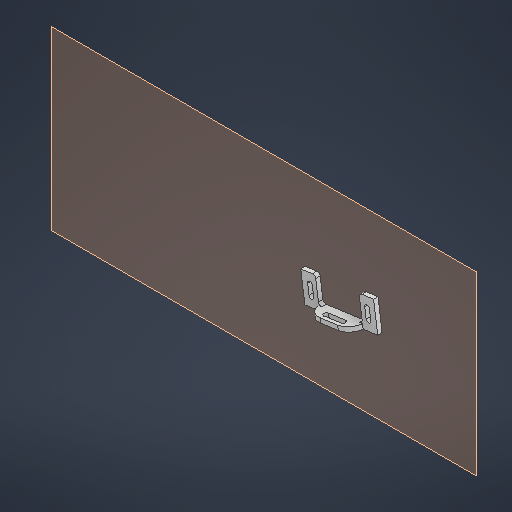
# Autodesk Inventor part: support_cable_aimant
Saved by Autodesk Inventor 2026.1 (Build 301233020, 233B)
## iProperties
Created: 2026-06-08
Part Number: support_cable_aimant
Material: Générique
Document SubType Name: Modeling
Designer: matpo
Density: 1 g/cm^3
Appearance: Par défaut
Author: matpo
Autodesk Inventor part; units mm, degrees
ref_plane "YZ Plane" through (0, 0, 0) normal (1, 0, 0) x (0, 1, 0)
ref_plane "XZ Plane" through (0, 0, 0) normal (0, 1, 0) x (-1, 0, 0)
ref_plane "XY Plane" through (0, 0, 0) normal (0, 0, 1) x (1, 0, 0)
ref_plane "Plan de construction1" through (0, 0, 0) normal (0, 0, 1) x (1, 0, 0)
sketch "Esquisse1" plane through (0, 0, 0) normal (0, 0, 1) x (1, 0, 0)
  line L0 (100.8988, -45.4881) -> (101.7309, -51.4301) projected
  arc A0 (104.0679, -45.0443) -> (100.8988, -45.4881) centre (102.4833, -45.2662) ccw projected
  line L1 (104.9, -50.9863) -> (104.0679, -45.0443) projected
  arc A1 (101.7309, -51.4301) -> (104.9, -50.9863) centre (103.3155, -51.2082) ccw projected
  line L2 (139.72, -40.0515) -> (140.5521, -45.9936) projected
  arc A2 (140.5521, -45.9936) -> (143.7212, -45.5498) centre (142.1366, -45.7717) ccw projected
  line L3 (143.7212, -45.5498) -> (142.889, -39.6077) projected
  arc A3 (142.889, -39.6077) -> (139.72, -40.0515) centre (141.3045, -39.8296) ccw projected
  line L4 (138.2745, -51.3613) -> (136.0555, -35.5159) projected
  arc A4 (136.5712, -53.6193) -> (138.2745, -51.3613) centre (136.2939, -51.6387) ccw projected
  line L5 (110.8225, -57.2252) -> (136.5712, -53.6193) projected
  arc A5 (108.5644, -55.5219) -> (110.8225, -57.2252) centre (110.5451, -55.2445) ccw projected
  line L6 (106.3454, -39.6765) -> (108.5644, -55.5219) projected
  arc A6 (106.3454, -39.6765) -> (104.0874, -37.9732) centre (104.3648, -39.9539) ccw projected
  line L7 (85.7294, -40.5441) -> (104.0874, -37.9732) projected
  arc A7 (137.7588, -33.2579) -> (136.0555, -35.5159) centre (138.0362, -35.2385) ccw projected
  line L8 (137.7588, -33.2579) -> (158.6909, -30.3265) projected
  line L9 (96.1647, -39.0827) -> (145.6815, -32.1484)
  line L10 (145.6815, -32.1484) -> (148.4553, -51.9551)
  line L11 (148.4553, -51.9551) -> (98.9385, -58.8895)
  line L12 (98.9385, -58.8895) -> (96.1647, -39.0827)
  line L13 (102.4833, -45.2662) -> (101.5125, -38.3338) construction
  line L14 (103.3155, -51.2082) -> (104.2863, -58.1406) construction
  line L15 (101.3149, -48.4591) -> (97.5516, -48.9861) construction
  line L16 (143.3051, -42.5787) -> (147.0684, -42.0517) construction
  circle A8 centre (102.8994, -48.2372) radius 1.6
  line L17 (123.6969, -55.4223) -> (120.9231, -35.6156) construction
  circle A9 centre (141.7206, -42.8006) radius 1.6
  line L18 (130.6487, -47.3804) -> (114.8034, -49.5994) projected
  arc A10 (130.6487, -47.3804) -> (129.8166, -41.4384) centre (130.2327, -44.4094) ccw projected
  line L19 (113.9712, -43.6574) -> (129.8166, -41.4384) projected
  arc A11 (113.9712, -43.6574) -> (114.8034, -49.5994) centre (114.3873, -46.6284) ccw projected
  line L20 (115.7742, -56.5318) -> (134.8636, -53.8585) construction
  line L21 (96.6362, -42.4499) -> (106.5396, -41.063)
  line L22 (136.2497, -36.9024) -> (146.153, -35.5155)
  line L23 (108.4257, -54.5316) -> (138.1358, -50.371)
  point P0 (0, 0)
  point P1 (125.3189, -55.1951)
  point P2 (113.7736, -53.7827)
  point P3 (96.1647, -39.0827)
  point P4 (145.6815, -32.1484)
  point P5 (104.4839, -48.0153)
  point P6 (140.136, -43.0225)
  point P7 (143.3051, -42.5787)
  point P8 (102.2614, -43.6817)
  point P9 (136.5712, -53.6193)
  dimension "d0" = 20
  dimension "d1" = 50
  dimension "d2" = 6
  dimension "d14" = 2
  dimension "d15" = 3
  constraints: 27 end point, 12 point on line, 9 parallel, 7 midpoint, 3 collinear, 2 perpendicular, 1 centre point, 1 point on circle, 1 symmetric about line, 5 other
  measures "d0" distance of L11.end L9.start
  measures "d1" distance of L10.end L11.end
  measures "d2" distance between parallel lines of L18 L19
  measures "d14" distance from line of point (102.261, -43.682) L21
  measures "d15" distance between parallel lines of L5 L23
extrude "Extrusion1" add sketch "Esquisse1" along normal blind 3 contours A0 L1 A8 L0 | A8 L1 A1 L0 | A3 L3 A9 L2 | A9 L3 A2 L2 | A4 L5 A5 L6 L23 L4 | L4 L22 L10 L11 A4 | L4 A7 L8 L10 L22 | L6 A5 L11 L12 L21 | L21 L12 L7 A6 L6
sketch "Esquisse3" plane through (0, 0, 3) normal (0, 0, 1) x (1, 0, 0)
  circle A0 centre (141.7206, -42.8006) radius 1.6 projected
  line L0 (98.9385, -58.8895) -> (148.4553, -51.9551) projected
  line L1 (148.4553, -51.9551) -> (145.6815, -32.1484) projected
  line L2 (145.6815, -32.1484) -> (137.7588, -33.2579) projected
  arc A1 (137.7588, -33.2579) -> (136.0555, -35.5159) centre (138.0362, -35.2385) ccw projected
  line L3 (136.0555, -35.5159) -> (138.1358, -50.371) projected
  line L4 (138.1358, -50.371) -> (108.4257, -54.5316) projected
  line L5 (108.4257, -54.5316) -> (106.3454, -39.6765) projected
  arc A2 (106.3454, -39.6765) -> (104.0874, -37.9732) centre (104.3648, -39.9539) ccw projected
  line L6 (104.0874, -37.9732) -> (96.1647, -39.0827) projected
  line L7 (96.1647, -39.0827) -> (98.9385, -58.8895) projected
  circle A3 centre (102.8994, -48.2372) radius 1.6 projected
  line L8 (108.4257, -54.5316) -> (108.8418, -57.5026)
  line L9 (138.1358, -50.371) -> (108.4257, -54.5316) projected
  line L10 (138.1358, -50.371) -> (138.5519, -53.342)
  line L11 (98.9385, -58.8895) -> (148.4553, -51.9551) projected
  point P0 (0, 0)
  constraints: 4 end point, 2 perpendicular, 2 point on line
extrude "Extrusion2" add sketch "Esquisse3" along normal blind 8 contours L8 L4 L10 L0
fillet "Congé1" radius 9 2 edges at (108.6338, -56.0171, 11) (138.3439, -51.8565, 11)
sketch "Esquisse4" plane through (148.4553, -51.9551, 3) normal (0.1386876, -0.9903362, 0) x (-0.9903362, -0.1386876, 0)
  arc A0 (31.0557, -8) -> (40, 0) centre (31.0557, 1) ccw
  line L0 (18.9443, -8) -> (31.0557, -8)
  arc A1 (10, 0) -> (18.9443, -8) centre (18.9443, 1) ccw
  line L1 (30.9, -4) -> (19.1, -4) construction
  line L2 (30.9, -2.4) -> (19.1, -2.4)
  line L3 (19.1, -5.6) -> (30.9, -5.6)
  arc A2 (30.9, -5.6) -> (30.9, -2.4) centre (30.9, -4) ccw
  arc A3 (19.1, -2.4) -> (19.1, -5.6) centre (19.1, -4) ccw
  line L4 (10, 0) -> (40, 0) construction
  line L5 (25, -4) -> (25, -8) construction
  line L6 (25, -4) -> (25, 0) construction
  line L7 (17.5, -4) -> (11.461, -4) construction
  line L8 (32.5, -4) -> (38.539, -4) construction
  arc A4 (10, 0) -> (18.9443, -8) centre (18.9443, 1) ccw projected
  line L9 (31.0557, -8) -> (18.9443, -8) projected
  arc A5 (31.0557, -8) -> (40, 0) centre (31.0557, 1) ccw projected
  line L10 (50, 0) -> (40, 0) projected
  line L11 (50, 3) -> (50, 0) projected
  line L12 (50, 3) -> (0, 3) projected
  line L13 (0, 3) -> (0, 0) projected
  line L14 (10, 0) -> (0, 0) projected
  point P0 (139.8151, 3)
  dimension "d9" = 3.2
  dimension "d13" = 15
  constraints: 20 end point, 12 point on circle, 4 centre point, 4 tangent, 3 midpoint, 3 parallel, 2 coincident, 2 collinear, 1 horizontal, 1 point on line
  measures "d9" diameter of A3
  measures "d13" distance of L7.start L8.start
extrude "Extrusion3" cut sketch "Esquisse4" against normal through all contours A2 L3 A3 L2
fillet "Congé2" radius 2 2 edges at (108.4257, -54.5316, 1.5) (138.1358, -50.371, 1.5)
sketch "Esquisse5" plane through (0, 0, 3) normal (0, 0, 1) x (1, 0, 0)
  circle A0 centre (102.8994, -48.2372) radius 1.6 projected
  circle A1 centre (141.7206, -42.8006) radius 1.6 projected
  line L0 (142.1921, -46.1678) -> (141.249, -39.4335) construction
  line L1 (143.7766, -45.9459) -> (142.8336, -39.2116)
  line L2 (139.6645, -39.6554) -> (140.6076, -46.3897)
  arc A2 (140.6076, -46.3897) -> (143.7766, -45.9459) centre (142.1921, -46.1678) ccw
  arc A3 (142.8336, -39.2116) -> (139.6645, -39.6554) centre (141.249, -39.4335) ccw
  line L3 (148.4553, -51.9551) -> (145.6815, -32.1484) construction
  line L4 (103.3709, -51.6043) -> (102.4279, -44.8701) construction
  line L5 (104.9555, -51.3824) -> (104.0124, -44.6482)
  line L6 (100.8433, -45.092) -> (101.7864, -51.8262)
  arc A4 (101.7864, -51.8262) -> (104.9555, -51.3824) centre (103.3709, -51.6043) ccw
  arc A5 (104.0124, -44.6482) -> (100.8433, -45.092) centre (102.4279, -44.8701) ccw
  point P0 (0, 0)
  point P1 (142.414, -47.7523)
  point P2 (141.0271, -37.849)
  dimension "d17" = 10
  constraints: 16 end point, 10 point on circle, 8 tangent, 5 parallel, 4 centre point, 2 equal radius, 2 midpoint, 1 coincident
  measures "d17" distance of point (142.414, -47.752) point (141.027, -37.849)
extrude "Extrusion4" cut sketch "Esquisse5" against normal through all
